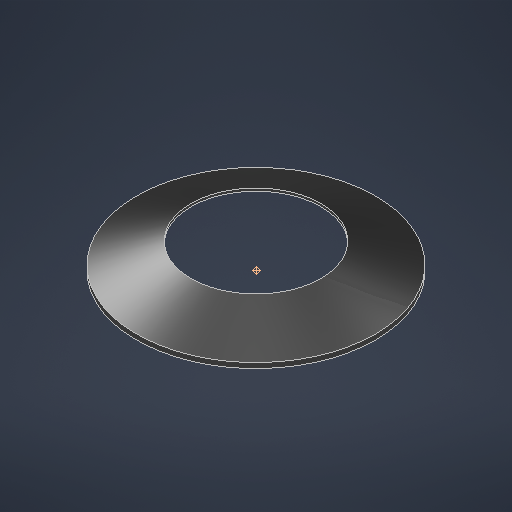
# Autodesk Inventor part: Spring wave washer
Saved by Autodesk Inventor 2026.3 (Build 303398000, 398)
## iProperties
Created: 2026-11-02
Part Number: Spring wave washer
Material: Stainless Steel
Document SubType Name: Modeling
Designer: ADMIN
Density: 8 g/cm^3
Appearance: Glossy - Black
Author: ADMIN
Autodesk Inventor part; units mm, degrees
ref_plane "YZ Plane" through (0, 0, 0) normal (1, 0, 0) x (0, 1, 0)
ref_plane "XZ Plane" through (0, 0, 0) normal (0, 1, 0) x (-1, 0, 0)
ref_plane "XY Plane" through (0, 0, 0) normal (0, 0, 1) x (1, 0, 0)
sketch "Sketch1" plane through (0, 0, 0) normal (0, 0, 1) x (1, 0, 0)
  line L0 (0, 2) -> (0, 0) construction
  line L1 (2.5, 1) -> (4.6, 0.2)
  line L2 (4.6, 0.2) -> (4.6, 0)
  line L3 (4.6, 0) -> (4.5, 0)
  line L4 (4.5, 0) -> (4.5, 0.1311)
  line L5 (4.5, 0.1311) -> (2.5, 0.893)
  line L6 (2.5, 0.893) -> (2.5, 1)
  point P0 (0, 1)
  dimension "d7" = 2
  dimension "d8" = 0.1
  dimension "d9" = 0.2
  dimension "d10" = 5
  dimension "d11" = 9
  dimension "d12" = 0.1
  constraints: 14 end point, 3 vertical alignment, 2 horizontal alignment, 2 parallel, 2 perpendicular, 1 coincident, 1 midpoint, 1 vertical
  measures "d7" distance of L0.start L0.end
  measures "d8" distance between parallel lines of L5 L1
  measures "d9" distance of L1.end L2.end
  measures "d10" diameter of L1.start L0
  measures "d11" diameter of L3.end L0
  measures "d12" distance of L2.end L3.end
revolve "Revolution1" add sketch "Sketch1" angle 360 about axis through (0, 2, 0) along (0, -1, 0)
body "Solid1"
